Autodesk Fusion 360 part; units mm, degrees
(part 2 of 2)
sketch "Skizze3" plane through (0, 0, 0) normal (0, 0, 1) x (1, 0, 0)
  circle A0 centre (0, 0) radius 30 construction
  spline S0 degree 3 poles (-17.884, 24.0022) (-17.9475, 24.0395) (-17.9858, 24.0887) (-17.9774, 24.1541) knots 0 0 0 0 1 1 1 1
  spline S1 degree 3 poles (-17.9774, 24.1541) (-17.7908, 25.4077) (-17.9848, 26.6869) (-18.5272, 27.8307) knots 0 0 0 0 1 1 1 1
  spline S2 degree 3 poles (-18.5272, 27.8307) (-18.574, 27.8731) (-18.601, 27.9202) (-18.5666, 27.9667) knots 0 0 0 0 1 1 1 1
  spline S3 degree 3 poles (-18.5666, 27.9667) (-18.5566, 28.0231) (-18.4759, 28.0636) (-18.3531, 28.0813) knots 0 0 0 0 1 1 1 1
  spline S4 degree 3 poles (-18.3531, 28.0813) (-18.0337, 28.2125) (-17.6429, 28.2766) (-17.3794, 28.4877) knots 0 0 0 0 1 1 1 1
  spline S5 degree 3 poles (-17.3794, 28.4877) (-17.1889, 28.6385) (-17.2498, 28.911) (-17.2498, 29.128) knots 0 0 0 0 1 1 1 1
  spline S6 degree 3 poles (-17.2498, 29.128) (-17.2498, 29.4084) (-17.2627, 29.673) (-17.2627, 29.9376) knots 0 0 0 0 1 1 1 1
  spline S7 degree 3 poles (-17.2627, 29.9376) (-17.2786, 30.4509) (-17.3114, 30.9721) (-17.3609, 31.5013) knots 0 0 0 0 1 1 1 1
  spline S8 degree 3 poles (-17.3609, 31.5013) (-17.4445, 32.408) (-17.5945, 33.3073) (-17.8104, 34.1921) knots 0 0 0 0 1 1 1 1
  spline S9 degree 3 poles (-17.8104, 34.1921) (-18.1353, 35.5595) (-18.6709, 36.8681) (-19.3979, 38.0709) knots 0 0 0 0 1 1 1 1
  spline S10 degree 3 poles (-19.3979, 38.0709) (-20.3451, 39.6081) (-21.6366, 40.7167) (-23.068, 41.7751) knots 0 0 0 0 1 1 1 1
  spline S11 degree 3 poles (-23.068, 41.7751) (-23.3325, 41.9682) (-23.83, 42.259) (-23.8617, 42.6268) knots 0 0 0 0 1 1 1 1
  spline S12 degree 3 poles (-23.8617, 42.6268) (-23.8797, 42.7313) (-23.8218, 42.8352) (-23.7239, 42.8757) knots 0 0 0 0 1 1 1 1
  spline S13 degree 3 poles (-23.7239, 42.8757) (-23.3074, 43.1168) (-22.8632, 43.3057) (-22.4009, 43.439) knots 0 0 0 0 1 1 1 1
  spline S14 degree 3 poles (-22.4009, 43.439) (-21.4368, 43.747) (-20.4356, 43.9251) (-19.4244, 43.9682) knots 0 0 0 0 1 1 1 1
  spline S15 degree 3 poles (-19.4244, 43.9682) (-17.3892, 44.0552) (-15.3532, 43.8245) (-13.3895, 43.2832) knots 0 0 0 0 1 1 1 1
  spline S16 degree 3 poles (-13.3895, 43.2832) (-12.5508, 43.0504) (-11.7412, 42.754) (-10.9183, 42.4894) knots 0 0 0 0 1 1 1 1
  spline S17 degree 3 poles (-10.9183, 42.4894) (-10.4881, 42.3516) (-10.0637, 42.196) (-9.6446, 42.0277) knots 0 0 0 0 1 1 1 1
  spline S18 degree 3 poles (-9.6446, 42.0277) (-9.643, 42.0444) (-9.6467, 42.0611) (-9.6322, 42.0764) knots 0 0 0 0 1 1 1 1
  spline S19 degree 3 poles (-9.6322, 42.0764) (-9.357, 42.3807) (-9.0768, 42.6773) (-8.7858, 42.9683) knots 0 0 0 0 1 1 1 1
  spline S20 degree 3 poles (-8.7858, 42.9683) (-6.599, 45.1361) (-4.0323, 46.8834) (-1.2136, 48.1227) knots 0 0 0 0 1 1 1 1
  spline S21 degree 3 poles (-1.2136, 48.1227) (1.4002, 49.2633) (4.1611, 50.0314) (6.9884, 50.4055) knots 0 0 0 0 1 1 1 1
  spline S22 degree 3 poles (6.9884, 50.4055) (8.2468, 50.5754) (9.5131, 50.6767) (10.7804, 50.7085) knots 0 0 0 0 1 1 1 1
  spline S23 degree 3 poles (10.7804, 50.7085) (12.0481, 50.7402) (13.3173, 50.7029) (14.5825, 50.5963) knots 0 0 0 0 1 1 1 1
  spline S24 degree 3 poles (14.5825, 50.5963) (16.5558, 50.4619) (18.5065, 50.0922) (20.3922, 49.4956) knots 0 0 0 0 1 1 1 1
  spline S25 degree 3 poles (20.3922, 49.4956) (21.0164, 49.3014) (21.6183, 49.0408) (22.1866, 48.718) knots 0 0 0 0 1 1 1 1
  spline S26 degree 3 poles (22.1866, 48.718) (22.5623, 48.5344) (22.8767, 48.2454) (23.0915, 47.8869) knots 0 0 0 0 1 1 1 1
  spline S27 degree 3 poles (23.0915, 47.8869) (23.1119, 47.8547) (23.1061, 47.8121) (23.078, 47.7861) knots 0 0 0 0 1 1 1 1
  spline S28 degree 3 poles (23.078, 47.7861) (22.5832, 47.1405) (21.8929, 46.736) (21.1971, 46.3471) knots 0 0 0 0 1 1 1 1
  spline S29 degree 3 poles (21.1971, 46.3471) (20.4589, 45.9348) (19.7514, 45.4697) (19.0804, 44.9554) knots 0 0 0 0 1 1 1 1
  spline S30 degree 3 poles (19.0804, 44.9554) (17.8168, 43.9902) (16.7066, 42.844) (15.7641, 41.5652) knots 0 0 0 0 1 1 1 1
  spline S31 degree 3 poles (15.7641, 41.5652) (16.8214, 41.6478) (17.88, 41.7229) (18.9402, 41.7695) knots 0 0 0 0 1 1 1 1
  spline S32 degree 3 poles (18.9402, 41.7695) (19.7922, 41.8224) (20.6468, 41.8224) (21.4987, 41.7695) knots 0 0 0 0 1 1 1 1
  spline S33 degree 3 poles (21.4987, 41.7695) (21.8877, 41.7219) (23.2685, 41.6187) (23.0277, 40.9281) knots 0 0 0 0 1 1 1 1
  spline S34 degree 3 poles (23.0277, 40.9281) (22.9105, 40.6744) (22.7359, 40.4519) (22.5174, 40.2775) knots 0 0 0 0 1 1 1 1
  spline S35 degree 3 poles (22.5174, 40.2775) (22.2104, 39.9785) (21.8821, 39.7137) (21.5567, 39.4491) knots 0 0 0 0 1 1 1 1
  spline S36 degree 3 poles (21.5567, 39.4491) (20.6775, 38.7501) (19.8636, 37.9727) (19.1251, 37.1263) knots 0 0 0 0 1 1 1 1
  spline S37 degree 3 poles (19.1251, 37.1263) (18.4372, 36.3053) (17.8313, 35.4192) (17.3157, 34.4805) knots 0 0 0 0 1 1 1 1
  spline S38 degree 3 poles (17.3157, 34.4805) (17.0881, 34.0572) (16.8791, 33.6206) (16.633, 33.2052) knots 0 0 0 0 1 1 1 1
  spline S39 degree 3 poles (16.633, 33.2052) (16.5658, 33.0528) (16.4626, 32.9226) (16.3383, 32.8165) knots 0 0 0 0 1 1 1 1
  spline S40 degree 3 poles (16.3383, 32.8165) (16.728, 32.6972) (17.1244, 32.5924) (17.5244, 32.4885) knots 0 0 0 0 1 1 1 1
  spline S41 degree 3 poles (17.5244, 32.4885) (17.8546, 32.4337) (18.1782, 32.345) (18.4901, 32.2239) knots 0 0 0 0 1 1 1 1
  spline S42 degree 3 poles (18.4901, 32.2239) (18.5272, 32.2053) (18.6386, 32.1339) (18.6174, 32.0704) knots 0 0 0 0 1 1 1 1
  spline S43 degree 3 poles (18.6174, 32.0704) (18.0856, 30.3665) (17.5773, 28.6517) (16.9952, 26.961) knots 0 0 0 0 1 1 1 1
  spline S44 degree 3 poles (16.9952, 26.961) (16.7936, 26.3766) (16.5997, 25.6913) (16.2526, 25.1479) knots 0 0 0 0 1 1 1 1
  spline S45 degree 3 poles (16.2526, 25.1479) (24.3859, 19.8334) (29.7656, 10.6466) (29.7656, 0.213) knots 0 0 0 0 1 1 1 1
  spline S46 degree 3 poles (29.7656, 0.213) (29.7656, -16.215) (16.4282, -29.5526) (0, -29.5526) knots 0 0 0 0 1 1 1 1
  spline S47 degree 3 poles (0, -29.5526) (-16.428, -29.5526) (-29.7656, -16.215) (-29.7656, 0.213) knots 0 0 0 0 1 1 1 1
  spline S48 degree 3 poles (-29.7656, 0.213) (-29.7656, 9.9319) (-25.0976, 18.5693) (-17.884, 24.0022) knots 0 0 0 0 1 1 1 1
  spline S49 degree 3 poles (23.8429, -14.5534) (22.7394, -14.8963) (21.5789, -15.2297) (20.3758, -15.5361) knots 0 0 0 0 1 1 1 1
  spline S50 degree 3 poles (20.3758, -15.5361) (16.2526, -16.587) (12.5328, -17.1119) (9.2321, -17.1119) knots 0 0 0 0 1 1 1 1
  spline S51 degree 3 poles (9.2321, -17.1119) (4.5048, -17.1119) (0.6374, -16.0356) (-2.3281, -13.8856) knots 0 0 0 0 1 1 1 1
  spline S52 degree 3 poles (-2.3281, -13.8856) (-2.7178, -13.6033) (-2.8226, -13.068) (-2.5699, -12.6593) knots 0 0 0 0 1 1 1 1
  spline S53 degree 3 poles (-2.5699, -12.6593) (-2.3164, -12.2499) (-1.7899, -12.1063) (-1.3639, -12.328) knots 0 0 0 0 1 1 1 1
  spline S54 degree 3 poles (-1.3639, -12.328) (-0.263, -12.9024) (1.0213, -13.34) (1.5748, -13.3482) knots 0 0 0 0 1 1 1 1
  spline S55 degree 3 poles (1.5748, -13.3482) (1.5071, -13.0236) (1.2099, -12.2039) (-0.0415, -10.4645) knots 0 0 0 0 1 1 1 1
  spline S56 degree 3 poles (-0.0415, -10.4645) (-0.2114, -10.2275) (-0.259, -9.9245) (-0.1701, -9.647) knots 0 0 0 0 1 1 1 1
  line L0 (-0.1701, -9.647) -> (2.2109, -2.24)
  spline S57 degree 3 poles (2.2109, -2.24) (2.2958, -1.9759) (2.4953, -1.7645) (2.7538, -1.6648) knots 0 0 0 0 1 1 1 1
  spline S58 degree 3 poles (2.7538, -1.6648) (3.0123, -1.5647) (3.302, -1.5864) (3.5425, -1.7248) knots 0 0 0 0 1 1 1 1
  spline S59 degree 3 poles (3.5425, -1.7248) (3.5687, -1.7396) (6.2061, -3.2512) (9.0689, -4.586) knots 0 0 0 0 1 1 1 1
  spline S60 degree 3 poles (9.0689, -4.586) (13.757, -6.772) (15.0995, -6.6604) (15.389, -6.5839) knots 0 0 0 0 1 1 1 1
  spline S61 degree 3 poles (15.389, -6.5839) (15.3612, -6.2809) (14.9672, -4.7892) (10.4095, -0.277) knots 0 0 0 0 1 1 1 1
  spline S62 degree 3 poles (10.4095, -0.277) (7.7036, 2.4019) (4.9019, 4.7829) (4.8742, 4.807) knots 0 0 0 0 1 1 1 1
  spline S63 degree 3 poles (4.8742, 4.807) (4.5752, 5.0607) (4.4704, 5.4766) (4.6135, 5.842) knots 0 0 0 0 1 1 1 1
  spline S64 degree 3 poles (4.6135, 5.842) (5.7714, 8.7985) (7.2993, 14.1351) (6.4709, 15.8692) knots 0 0 0 0 1 1 1 1
  spline S65 degree 3 poles (6.4709, 15.8692) (6.3526, 16.1166) (6.2272, 16.1848) (6.1203, 16.2187) knots 0 0 0 0 1 1 1 1
  line L1 (6.1203, 16.2187) -> (5.8658, 16.2994)
  spline S66 degree 3 poles (5.8658, 16.2994) (5.7632, 16.3322) (5.6115, 16.3518) (5.3568, 16.2123) knots 0 0 0 0 1 1 1 1
  spline S67 degree 3 poles (5.3568, 16.2123) (3.6441, 15.2747) (1.6981, 10.065) (0.8742, 7.0017) knots 0 0 0 0 1 1 1 1
  spline S68 degree 3 poles (0.8742, 7.0017) (0.7742, 6.6302) (0.4535, 6.3603) (0.0709, 6.3254) knots 0 0 0 0 1 1 1 1
  spline S69 degree 3 poles (0.0709, 6.3254) (0.0341, 6.3222) (-3.6269, 5.9843) (-7.3808, 5.348) knots 0 0 0 0 1 1 1 1
  spline S70 degree 3 poles (-7.3808, 5.348) (-13.6599, 4.2839) (-14.8675, 3.2962) (-15.0791, 3.0483) knots 0 0 0 0 1 1 1 1
  spline S71 degree 3 poles (-15.0791, 3.0483) (-14.8828, 2.816) (-13.8388, 1.9547) (-8.7511, 1.0501) knots 0 0 0 0 1 1 1 1
  spline S72 degree 3 poles (-8.7511, 1.0501) (-5.6414, 0.4972) (-2.6249, 0.2191) (-2.5948, 0.2162) knots 0 0 0 0 1 1 1 1
  spline S73 degree 3 poles (-2.5948, 0.2162) (-2.3188, 0.1913) (-2.0688, 0.0426) (-1.9151, -0.1879) knots 0 0 0 0 1 1 1 1
  spline S74 degree 3 poles (-1.9151, -0.1879) (-1.7608, -0.4183) (-1.719, -0.7062) (-1.8013, -0.9708) knots 0 0 0 0 1 1 1 1
  line L2 (-1.8013, -0.9708) -> (-4.1116, -8.4008)
  spline S75 degree 3 poles (-4.1116, -8.4008) (-4.1981, -8.6791) (-4.4117, -8.8998) (-4.6868, -8.9956) knots 0 0 0 0 1 1 1 1
  spline S76 degree 3 poles (-4.6868, -8.9956) (-6.7088, -9.6988) (-7.4237, -10.1981) (-7.6668, -10.4251) knots 0 0 0 0 1 1 1 1
  spline S77 degree 3 poles (-7.6668, -10.4251) (-7.2054, -10.7352) (-5.8838, -11.1218) (-4.6765, -11.2802) knots 0 0 0 0 1 1 1 1
  spline S78 degree 3 poles (-4.6765, -11.2802) (-4.3238, -11.3265) (-4.0299, -11.5723) (-3.9214, -11.9113) knots 0 0 0 0 1 1 1 1
  spline S79 degree 3 poles (-3.9214, -11.9113) (-3.8129, -12.2502) (-3.9103, -12.6212) (-4.1706, -12.8632) knots 0 0 0 0 1 1 1 1
  spline S80 degree 3 poles (-4.1706, -12.8632) (-6.2161, -14.7656) (-11.0715, -15.4244) (-18.6018, -14.8225) knots 0 0 0 0 1 1 1 1
  spline S81 degree 3 poles (-18.6018, -14.8225) (-20.5441, -14.6672) (-22.4242, -14.4457) (-24.0443, -14.2237) knots 0 0 0 0 1 1 1 1
  spline S82 degree 3 poles (-24.0443, -14.2237) (-19.1365, -22.375) (-10.2005, -27.8328) (0.0003, -27.8328) knots 0 0 0 0 1 1 1 1
  spline S83 degree 3 poles (0.0003, -27.8328) (10.0629, -27.8328) (18.8952, -22.5216) (23.8429, -14.5534) knots 0 0 0 0 1 1 1 1
  spline S84 degree 3 poles (25.1568, -12.1901) (27.0065, -8.4495) (28.0461, -4.2386) (28.0461, 0.213) knots 0 0 0 0 1 1 1 1
  spline S85 degree 3 poles (28.0461, 0.213) (28.0461, 15.6919) (15.4789, 28.2591) (0.0003, 28.2591) knots 0 0 0 0 1 1 1 1
  spline S86 degree 3 poles (0.0003, 28.2591) (-0.989, 28.2591) (-1.9661, 28.2078) (-2.9292, 28.1075) knots 0 0 0 0 1 1 1 1
  line L3 (-2.9292, 28.1075) -> (-3.6468, 28.0236)
  spline S87 degree 3 poles (-3.6468, 28.0236) (-17.4043, 26.2348) (-28.0456, 14.4568) (-28.0456, 0.213) knots 0 0 0 0 1 1 1 1
  spline S88 degree 3 poles (-28.0456, 0.213) (-28.0456, -4.2511) (-27.0005, -8.473) (-25.1415, -12.2208) knots 0 0 0 0 1 1 1 1
  spline S89 degree 3 poles (-25.1415, -12.2208) (-19.6821, -13.0347) (-11.5919, -13.7948) (-7.4213, -12.5447) knots 0 0 0 0 1 1 1 1
  spline S90 degree 3 poles (-7.4213, -12.5447) (-8.5389, -12.1573) (-9.4983, -11.5517) (-9.5949, -10.6093) knots 0 0 0 0 1 1 1 1
  spline S91 degree 3 poles (-9.5949, -10.6093) (-9.7171, -9.4168) (-8.5561, -8.4516) (-5.7293, -7.4176) knots 0 0 0 0 1 1 1 1
  line L4 (-5.7293, -7.4176) -> (-3.8896, -1.5018)
  spline S92 degree 3 poles (-3.8896, -1.5018) (-7.5496, -1.1152) (-15.2204, -0.0611) (-16.642, 2.0772) knots 0 0 0 0 1 1 1 1
  spline S93 degree 3 poles (-16.642, 2.0772) (-16.945, 2.5326) (-17.0249, 3.057) (-16.8677, 3.5544) knots 0 0 0 0 1 1 1 1
  spline S94 degree 3 poles (-16.8677, 3.5544) (-16.5325, 4.6151) (-15.199, 5.8693) (-7.852, 7.1308) knots 0 0 0 0 1 1 1 1
  spline S95 degree 3 poles (-7.852, 7.1308) (-4.8998, 7.6375) (-1.9764, 7.9632) (-0.7271, 8.092) knots 0 0 0 0 1 1 1 1
  spline S96 degree 3 poles (-0.7271, 8.092) (-0.1164, 10.1904) (1.8791, 16.4015) (4.4744, 17.8229) knots 0 0 0 0 1 1 1 1
  spline S97 degree 3 poles (4.4744, 17.8229) (5.1123, 18.1721) (5.7854, 18.2515) (6.4206, 18.0499) knots 0 0 0 0 1 1 1 1
  line L5 (6.4206, 18.0499) -> (6.6749, 17.9692)
  spline S98 degree 3 poles (6.6749, 17.9692) (7.3126, 17.7676) (7.8153, 17.3149) (8.1283, 16.66) knots 0 0 0 0 1 1 1 1
  spline S99 degree 3 poles (8.1283, 16.66) (9.3895, 14.0192) (7.3157, 7.8512) (6.5548, 5.783) knots 0 0 0 0 1 1 1 1
  spline S100 degree 3 poles (6.5548, 5.783) (7.5094, 4.9535) (9.7049, 3.0136) (11.82, 0.9107) knots 0 0 0 0 1 1 1 1
  spline S101 degree 3 poles (11.82, 0.9107) (17.1061, -4.345) (17.4763, -6.1378) (17.1405, -7.1988) knots 0 0 0 0 1 1 1 1
  spline S102 degree 3 poles (17.1405, -7.1988) (16.9833, -7.6959) (16.6164, -8.0793) (16.107, -8.2775) knots 0 0 0 0 1 1 1 1
  spline S103 degree 3 poles (16.107, -8.2775) (13.7144, -9.2101) (6.8315, -5.6621) (3.6147, -3.8746) knots 0 0 0 0 1 1 1 1
  line L6 (3.6147, -3.8746) -> (1.719, -9.7724)
  spline S104 degree 3 poles (1.719, -9.7724) (3.3584, -12.1304) (3.7936, -13.5652) (3.1475, -14.4783) knots 0 0 0 0 1 1 1 1
  spline S105 degree 3 poles (3.1475, -14.4783) (8.446, -15.9837) (14.891, -15.0363) (19.8924, -13.7642) knots 0 0 0 0 1 1 1 1
  spline S106 degree 3 poles (19.8924, -13.7642) (21.7636, -13.2882) (23.5442, -12.7407) (25.1568, -12.1901) knots 0 0 0 0 1 1 1 1
  spline S107 degree 3 poles (14.7712, 26.0554) (10.4166, 28.5517) (5.3737, 29.9786) (0, 29.9786) knots 0 0 0 0 1 1 1 1
  spline S108 degree 3 poles (0, 29.9786) (-6.1129, 29.9786) (-11.7978, 28.1321) (-16.5269, 24.9663) knots 0 0 0 0 1 1 1 1
  spline S109 degree 3 poles (-16.5269, 24.9663) (-16.678, 25.7418) (-16.6465, 26.5546) (-16.8637, 27.3188) knots 0 0 0 0 1 1 1 1
  spline S110 degree 3 poles (-16.8637, 27.3188) (-14.9924, 28.656) (-12.6582, 29.3706) (-10.4632, 29.9717) knots 0 0 0 0 1 1 1 1
  spline S111 degree 3 poles (-10.4632, 29.9717) (-8.1256, 30.6009) (-5.756, 31.1047) (-3.3644, 31.4801) knots 0 0 0 0 1 1 1 1
  spline S112 degree 3 poles (-3.3644, 31.4801) (-0.0085, 32.035) (3.3787, 32.3831) (6.7773, 32.5226) knots 0 0 0 0 1 1 1 1
  spline S113 degree 3 poles (6.7773, 32.5226) (7.6417, 32.5557) (8.5138, 32.5776) (9.3879, 32.5797) knots 0 0 0 0 1 1 1 1
  spline S114 degree 3 poles (9.3879, 32.5797) (11.8774, 32.5858) (14.3846, 32.4207) (16.8002, 31.8802) knots 0 0 0 0 1 1 1 1
  spline S115 degree 3 poles (16.8002, 31.8802) (16.1211, 30.0424) (15.5975, 28.1506) (14.8683, 26.3337) knots 0 0 0 0 1 1 1 1
  spline S116 degree 3 poles (14.8683, 26.3337) (14.8407, 26.2631) (14.8087, 26.1639) (14.7712, 26.0554) knots 0 0 0 0 1 1 1 1
  spline S117 degree 3 poles (-17.8869, 42.966) (-16.479, 42.9739) (-15.0744, 42.8167) (-13.7017, 42.4971) knots 0 0 0 0 1 1 1 1
  spline S118 degree 3 poles (-13.7017, 42.4971) (-10.241, 41.7245) (-6.8223, 40.1317) (-4.2929, 37.6182) knots 0 0 0 0 1 1 1 1
  spline S119 degree 3 poles (-4.2929, 37.6182) (-2.9149, 36.2892) (-1.8907, 34.639) (-1.3044, 32.8176) knots 0 0 0 0 1 1 1 1
  spline S120 degree 3 poles (-1.3044, 32.8176) (-2.9062, 32.4414) (-4.5326, 32.2024) (-6.1449, 31.917) knots 0 0 0 0 1 1 1 1
  spline S121 degree 3 poles (-6.1449, 31.917) (-8.1836, 31.5701) (-10.1973, 31.0885) (-12.1727, 30.4771) knots 0 0 0 0 1 1 1 1
  spline S122 degree 3 poles (-12.1727, 30.4771) (-13.3633, 30.1027) (-14.5362, 29.6783) (-15.6975, 29.2187) knots 0 0 0 0 1 1 1 1
  spline S123 degree 3 poles (-15.6975, 29.2187) (-15.743, 31.0639) (-16.0274, 32.8959) (-16.5486, 34.6681) knots 0 0 0 0 1 1 1 1
  spline S124 degree 3 poles (-16.5486, 34.6681) (-17.1424, 36.5355) (-18.1356, 38.2508) (-19.459, 39.6952) knots 0 0 0 0 1 1 1 1
  spline S125 degree 3 poles (-19.459, 39.6952) (-20.2885, 40.5905) (-21.2148, 41.3906) (-22.2165, 42.0878) knots 0 0 0 0 1 1 1 1
  spline S126 degree 3 poles (-22.2165, 42.0878) (-21.0465, 42.626) (-19.7792, 42.922) (-18.4904, 42.9525) knots 0 0 0 0 1 1 1 1
  spline S127 degree 3 poles (-18.4904, 42.9525) (-18.2893, 42.9601) (-18.088, 42.9646) (-17.8869, 42.966) knots 0 0 0 0 1 1 1 1
  spline S128 degree 3 poles (12.7847, 49.7303) (13.3435, 49.7231) (13.9028, 49.6985) (14.4629, 49.6517) knots 0 0 0 0 1 1 1 1
  spline S129 degree 3 poles (14.4629, 49.6517) (16.9095, 49.4451) (19.309, 48.8259) (21.4228, 47.5726) knots 0 0 0 0 1 1 1 1
  spline S130 degree 3 poles (21.4228, 47.5726) (19.4567, 46.5093) (17.6572, 45.1617) (16.0877, 43.5689) knots 0 0 0 0 1 1 1 1
  spline S131 degree 3 poles (16.0877, 43.5689) (15.6821, 43.1509) (15.2977, 42.7151) (14.9344, 42.2619) knots 0 0 0 0 1 1 1 1
  spline S132 degree 3 poles (14.9344, 42.2619) (14.773, 42.0608) (14.6696, 41.8568) (14.4949, 41.6743) knots 0 0 0 0 1 1 1 1
  spline S133 degree 3 poles (14.4949, 41.6743) (14.2936, 41.4988) (14.0547, 41.3721) (13.7964, 41.3038) knots 0 0 0 0 1 1 1 1
  spline S134 degree 3 poles (13.7964, 41.3038) (12.8677, 41.0234) (11.8943, 40.894) (10.9604, 40.6268) knots 0 0 0 0 1 1 1 1
  spline S135 degree 3 poles (10.9604, 40.6268) (9.5298, 40.2275) (8.1717, 39.6023) (6.9384, 38.7747) knots 0 0 0 0 1 1 1 1
  spline S136 degree 3 poles (6.9384, 38.7747) (4.8429, 37.3512) (3.1681, 35.4198) (1.7738, 33.3214) knots 0 0 0 0 1 1 1 1
  spline S137 degree 3 poles (1.7738, 33.3214) (1.7605, 33.3034) (1.7537, 33.2819) (1.7537, 33.2594) knots 0 0 0 0 1 1 1 1
  spline S138 degree 3 poles (1.7537, 33.2594) (1.7537, 33.2475) (1.7587, 33.2367) (1.7624, 33.2261) knots 0 0 0 0 1 1 1 1
  spline S139 degree 3 poles (1.7624, 33.2261) (1.1946, 33.1713) (0.6279, 33.1057) (0.0614, 33.0351) knots 0 0 0 0 1 1 1 1
  spline S140 degree 3 poles (0.0614, 33.0351) (-1.6198, 36.613) (-4.5786, 39.5295) (-8.0896, 41.3224) knots 0 0 0 0 1 1 1 1
  spline S141 degree 3 poles (-8.0896, 41.3224) (-8.3569, 41.4592) (-8.6281, 41.5875) (-8.9014, 41.711) knots 0 0 0 0 1 1 1 1
  spline S142 degree 3 poles (-8.9014, 41.711) (-8.7969, 41.7203) (-8.7003, 41.7438) (-8.6373, 41.8042) knots 0 0 0 0 1 1 1 1
  spline S143 degree 3 poles (-8.6373, 41.8042) (-5.756, 44.6035) (-2.3963, 46.9027) (1.4322, 48.1965) knots 0 0 0 0 1 1 1 1
  spline S144 degree 3 poles (1.4322, 48.1965) (3.4843, 48.8683) (5.6092, 49.2951) (7.7616, 49.4668) knots 0 0 0 0 1 1 1 1
  spline S145 degree 3 poles (7.7616, 49.4668) (9.4364, 49.6176) (11.108, 49.7517) (12.7847, 49.7303) knots 0 0 0 0 1 1 1 1
  spline S146 degree 3 poles (18.2782, 40.8691) (19.2974, 40.8882) (20.315, 40.7988) (21.3199, 40.6236) knots 0 0 0 0 1 1 1 1
  spline S147 degree 3 poles (21.3199, 40.6236) (20.243, 39.5452) (19.0847, 38.5464) (18.0536, 37.42) knots 0 0 0 0 1 1 1 1
  spline S148 degree 3 poles (18.0536, 37.42) (16.8757, 36.1302) (15.9258, 34.6504) (15.2387, 33.0451) knots 0 0 0 0 1 1 1 1
  spline S149 degree 3 poles (15.2387, 33.0451) (11.185, 33.5444) (7.0951, 33.6402) (3.0276, 33.3325) knots 0 0 0 0 1 1 1 1
  spline S150 degree 3 poles (3.0276, 33.3325) (3.8187, 34.2273) (4.4519, 35.2565) (5.2559, 36.1397) knots 0 0 0 0 1 1 1 1
  spline S151 degree 3 poles (5.2559, 36.1397) (6.2566, 37.2041) (7.4451, 38.0751) (8.7617, 38.7088) knots 0 0 0 0 1 1 1 1
  spline S152 degree 3 poles (8.7617, 38.7088) (11.2961, 40.0079) (14.2677, 40.5956) (17.0881, 40.8019) knots 0 0 0 0 1 1 1 1
  spline S153 degree 3 poles (17.0881, 40.8019) (17.4845, 40.8392) (17.8813, 40.8615) (18.2782, 40.8691) knots 0 0 0 0 1 1 1 1
  arc A1 (-17.3411, 28.5232) -> (-21.5027, 20.7869) centre (-20.2838, 25.1187) ccw
  arc A2 (-15.7953, 25.4408) -> (-15.8001, 25.5021) centre (-20.2838, 25.1187) ccw
  arc A3 (14.155, 26.4507) -> (14.1496, 26.4019) centre (18.6253, 25.9352) ccw
  arc A4 (20.4586, 21.8255) -> (16.0192, 29.6037) centre (18.6253, 25.9352) ccw
  arc A5 (18.6132, 23.4352) -> (17.3766, 28.101) centre (18.6253, 25.9352) ccw
  arc A6 (-17.9922, 26.1179) -> (-19.4021, 22.7793) centre (-20.2838, 25.1187) ccw
  arc A7 (-18.1697, 23.7843) -> (-18.1697, 23.7843) centre (-20.2838, 25.1187) ccw
  arc A8 (-17.9774, 24.1541) -> (-17.9774, 24.1541) centre (-20.2838, 25.1187) ccw
  dimension "d21" = 5
  dimension "d23" = 5
  constraint concentric A1 A7
  constraint coincident S5 A1.start
  constraint coincident A0 A2.end
  constraint coincident S108 A2.start
  constraint concentric A1 A2
  constraint coincident S48 A1.end
  constraint coincident S48 A6.end
  constraint coincident S48 A7.start
  constraint concentric A3 A5
  constraint coincident S115 A4.end
  constraint coincident A0 A3.start
  constraint coincident S107 A3.end
  constraint concentric A3 A4
  constraint coincident S45 A4.start
  constraint coincident S45 A5.start
  constraint coincident S43 A5.end
  constraint coincident S1 A6.start
  constraint concentric A6 A7
  constraint concentric A7 A8
  measures "d21" diameter of A7
  measures "d23" diameter of A5
extrude "Extrusion5" add sketch "Skizze3" against normal blind 1.5 separate body contours S0 S1 S2 S3 S4 S5 S6 S7 S8 S9 S10 S11 S12 S13 S14 S15 S16 S17 S18 S19 S20 S21 S22 S23 S24 S25 S26 S27 S28 S29 S30 S31 S32 S33 S34 S35 S36 S37 S38 S39 S40 S41 S42 S43 S44 S45 S46 S47 S48 A7 A8 | S1 A7 A8 | S48 A7 A8 | S1 S2 S3 S4 S5 S48 A1 A6 A7 A8 | S43 S45 A4 A5 | S49 S50 S51 S52 S53 S54 S55 S56 L0 S57 S58 S59 S60 S61 S62 S63 S64 S65 L1 S66 S67 S68 S69 S70 S71 S72 S73 S74 L2 S75 S76 S77 S78 S79 S80 S81 S82 S83 | S84 S85 S86 L3 S87 S88 S89 S90 S91 L4 S92 S93 S94 S95 S96 S97 L5 S98 S99 S100 S101 S102 S103 L6 S104 S105 S106 | S107 S108 S109 S110 S111 S112 S113 S114 S115 S116 | S117 S118 S119 S120 S121 S122 S123 S124 S125 S126 S127 | S128 S129 S130 S131 S132 S133 S134 S135 S136 S137 S138 S139 S140 S141 S142 S143 S144 S145 | S146 S147 S148 S149 S150 S151 S152 S153 makes body 3
extrude "Extrusion6" add sketch "Skizze3" along normal blind 1 contours S0 S1 S2 S3 S4 S5 S6 S7 S8 S9 S10 S11 S12 S13 S14 S15 S16 S17 S18 S19 S20 S21 S22 S23 S24 S25 S26 S27 S28 S29 S30 S31 S32 S33 S34 S35 S36 S37 S38 S39 S40 S41 S42 S43 S44 S45 S46 S47 S48 A7 A8 | S1 A7 A8 | S48 A7 A8 | S1 S2 S3 S4 S5 S48 A1 A6 A7 A8 | S43 S45 A4 A5 bodies 3
hidden bodies 2 3
named bodies: "YFU-Karnevalsorden", "AP-Karnevalsorden", "EP-Karnevalsorden"
